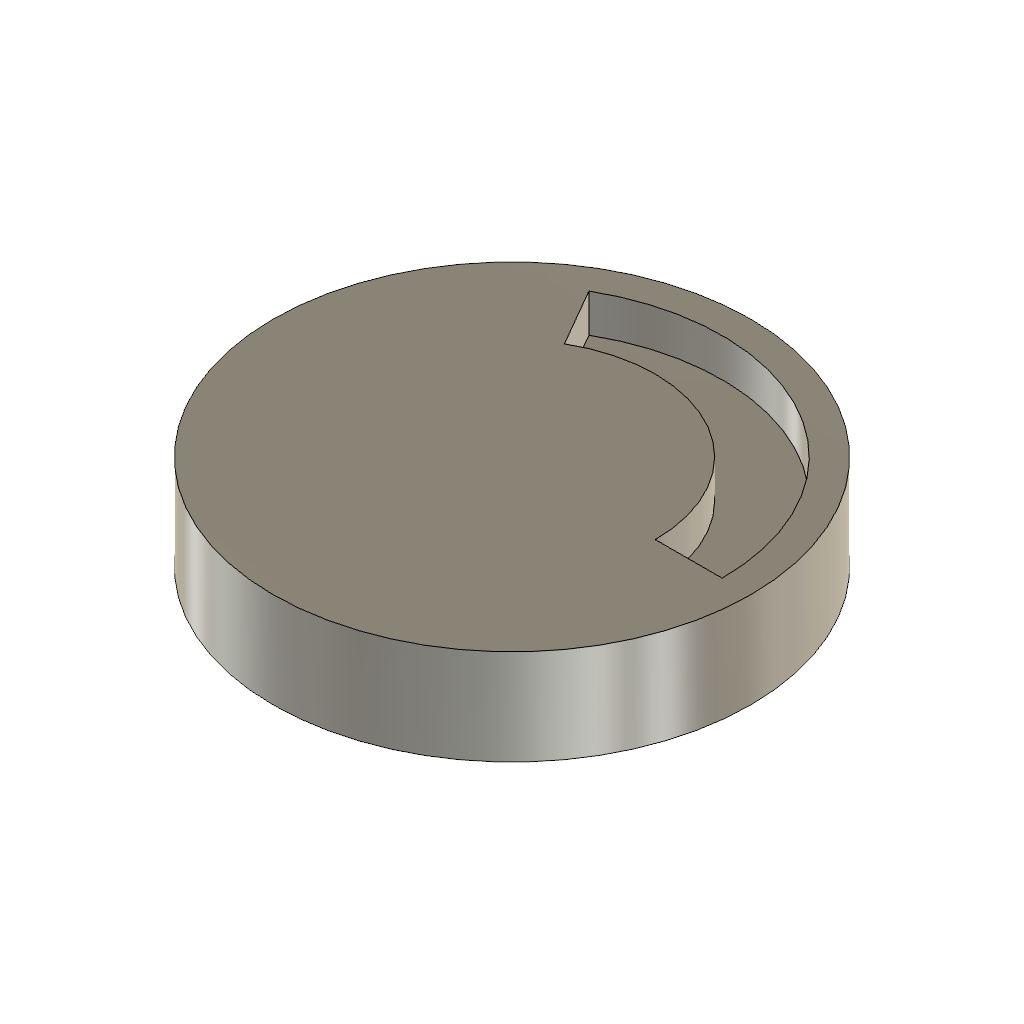
vendor_RevolveCut (Autodesk Fusion 360 design; units mm, degrees)
Autodesk Fusion 360 part; units mm, degrees
sketch "Disc sketch" plane through (0, 0, 0) normal (0, 0, 1) x (1, 0, 0)
  circle A0 centre (0, 0) radius 25
extrude "Disc extrude" add sketch "Disc sketch" along normal blind 10
sketch "Groove sketch" plane through (0, 0, 0) normal (0, 1, 0) x (1, 0, 0)
  line L0 (15, -6) -> (22, -6)
  line L1 (22, -6) -> (22, -10)
  line L2 (22, -10) -> (15, -10)
  line L3 (15, -10) -> (15, -6)
revolve "Groove revolve" cut sketch "Groove sketch" angle 120 about axis through (0, 0, 0) along (0, 0, 1)
equation "height = 20.0 mm"
